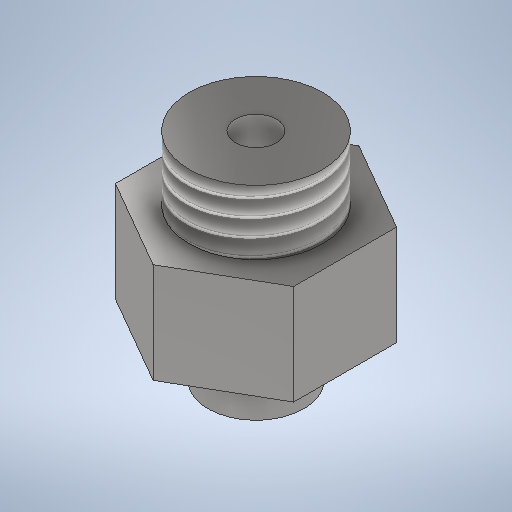
# Autodesk Inventor part: Металлическая часть
Saved by Autodesk Inventor 2025.1 (Build 291241000, 241)
## iProperties
Created: 2026-10-22
Part Number: Металлическая часть
Material: Сталь нержавеющая, 440C
Document SubType Name: Modeling
Designer: Ваня
Density: 7.75 g/cm^3
Appearance: С умеренной полировкой
Author: Ваня
Autodesk Inventor part; units mm, degrees
ref_plane "YZ Plane" through (0, 0, 0) normal (1, 0, 0) x (0, 1, 0)
ref_plane "XZ Plane" through (0, 0, 0) normal (0, 1, 0) x (-1, 0, 0)
ref_plane "XY Plane" through (0, 0, 0) normal (0, 0, 1) x (1, 0, 0)
sketch "Эскиз1" plane through (0, 0, 0) normal (0, 1, 0) x (-1, 0, 0)
  line L0 (0, 0) -> (6.5, 0)
  line L1 (6.5, 0) -> (6.5, 4)
  line L2 (6.5, 4) -> (6.5, -4)
  line L3 (-0.2141, 7.6292) -> (6.7141, 3.6292)
  line L4 (-6.7141, 3.6292) -> (0.2141, 7.6292)
  line L5 (-6.5, -4) -> (-6.5, 4)
  line L6 (0.2141, -7.6292) -> (-6.7141, -3.6292)
  line L7 (6.7141, -3.6292) -> (-0.2141, -7.6292)
  point P0 (0, -7.5056)
  point P1 (6.5, -3.7528)
  point P2 (6.5, 3.7528)
  point P3 (0, 7.5056)
  point P4 (-6.5, 3.7528)
  point P5 (-6.5, -3.7528)
  dimension "d0" = 6.5
  dimension "d1" = 4
  dimension "d2" = 8
  dimension "d5" = 360
  constraints: 16 end point, 2 coincident, 1 horizontal, 1 perpendicular, 1 point on line, 23 other
  measures "d0" distance of L0.start L0.end
  measures "d1" distance of L0.end L1.end
  measures "d2" distance of L1.end L2.end
extrude "Выдавливание1" add sketch "Эскиз1" along normal blind 7.3
sketch "Эскиз2" plane through (0, 7.3, 0) normal (0, 1, 0) x (1, 0, 0)
  circle A0 centre (0, 0) radius 4.864
  dimension "d9" = 9.728
  constraints: 1 centre point, 1 coincident
  measures "d9" diameter of A0
extrude "Выдавливание2" add sketch "Эскиз2" along normal blind 4.7
thread "Резьба1" size "M9x1.25" class "6g" standard "ANSI Metric M Profile" full length
sketch "Эскиз3" plane through (0, 0, 0) normal (0, -1, 0) x (1, 0, 0)
  circle A0 centre (0, 0) radius 3.5
  dimension "d14" = 7
  constraints: 1 centre point, 1 coincident
  measures "d14" diameter of A0
extrude "Выдавливание3" add sketch "Эскиз3" along normal blind 3.8
sketch "Эскиз4" plane through (0, -3.8, 0) normal (0, -1, 0) x (1, 0, 0)
  circle A0 centre (0, 0) radius 1.5
  dimension "d17" = 3
  constraints: 1 centre point, 1 coincident
  measures "d17" diameter of A0
extrude "Выдавливание4" cut sketch "Эскиз4" against normal blind 21
sketch "Эскиз5" plane through (0, 7.3, 0) normal (0, 1, 0) x (1, 0, 0)
  point P0 (0, 0)
